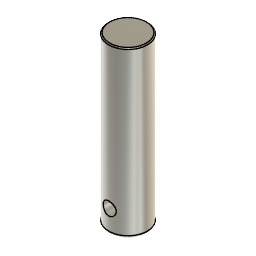
full hammer (Autodesk Fusion 360 archive; units mm, degrees)
design "hammer"
part number: 2025-10-12-17-45-08-986
Autodesk Fusion 360 part; units mm, degrees
sketch "handle" plane through (0, 0, 0) normal (0, 1, 0) x (1, 0, 0)
  line L0 (0, -14.3854) -> (0, -177.8)
  line L1 (0, -177.8) -> (0, -127.8)
  line L2 (0, -177.8) -> (19.05, -177.8)
  line L3 (19.05, -177.8) -> (19.05, -14.3854)
  line L4 (19.05, -14.3854) -> (0, -14.3854)
  dimension "d2" = 177.8
  constraint parallel L0 L1
  constraint perpendicular L1 L2
  constraint perpendicular L3 L4
  measures "d2" distance of origin L0.end
revolve "Revolve1" add sketch "handle" angle 360 about axis through (0, 0, 14.3854) along (0, 0, 1)
fillet "Fillet1" radius 3 1 edges at (-17.7608, -6.8888, 14.3854) 1 faces at (-7.2281, 0.9464, 14.3854)
sketch "hole" plane through (0, 0, 0) normal (0, 1, 0) x (1, 0, 0)
  line L0 (0, 0) -> (0, -32.4031)
  circle A0 centre (0, -32.4031) radius 6.35
  dimension "d10" = 12.7
  constraint coincident L0.start origin
  constraint vertical L0
  constraint coincident L0.end A0.centre
  measures "d10" diameter of A0
hole "Hole2" at (0, -19.05, 32.7368) direction (0, 1, 0) diameter 12.7 end through all
move_face "MoveFace1" to x (1, 0, 0) y (0, 1, 0) z (0, 0, 1) at (0, 0, 15) 1 faces at (8.4885, 17.0543, 76.1675)
move_face "MoveFace2" to x (0.939693, 0, 0.34202) y (0, 1, 0) z (-0.34202, 0, 0.939693) at (11.3236, 0, 11.9735) 1 faces at (1.7932, 6.3315, 26.6452)
move_face "MoveFace3" to x (0.965926, 0, -0.258819) y (0, 1, 0) z (0.258819, 0, 0.965926) at (-11.1135, 0, -3.5106) 1 faces at (-4.0829, 6.1688, 37.982)
fillet "Fillet6" radius 1 1 edges at (-17.7608, -6.8888, 177.8)
move_face "OffsetFaces1" offset -1 1 faces at (-8.3651, -1.4992, 14.3854)
named bodies: "handle"

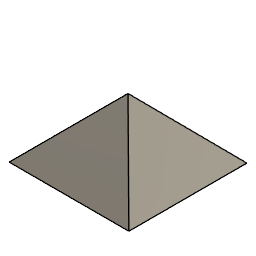
design "spike"
part number: 2025-10-12-19-42-02-121
Autodesk Fusion 360 part; units mm, degrees
sketch "base" plane through (0, 0, 0) normal (0, 0, 1) x (1, 0, 0)
  line L0 (25.4, -25.0465) -> (-25.4, -25.0465)
  line L1 (-25.4, -25.0465) -> (-25.4, 25.0465)
  line L2 (-25.4, 25.0465) -> (25.4, 25.0465)
  line L3 (25.4, 25.0465) -> (25.4, -25.0465)
  line L4 (25.4, -25.0465) -> (-25.4, 25.0465) construction
  line L5 (-25.4, -25.0465) -> (25.4, 25.0465) construction
  dimension "d18" = 50.8
  dimension "d19" = 50.093
  constraint horizontal L0
  constraint perpendicular L0 L1
  constraint parallel L0 L2
  constraint parallel L1 L3
  constraint coincident L4 origin
  constraint coincident L5 origin
  measures "d18" distance of L1.end L2.end
  measures "d19" distance of L0.end L1.end
ref_plane "WorkPlane3" through (0, 0, 25.4) normal (0, 0, 1) x (1, 0, 0)
sketch "Sketch6" plane through (0, 0, 25.4) normal (0, 0, 1) x (1, 0, 0)
loft "Loft2" add profiles "base" section 1 section 2 point at (0, 0, 25.4)

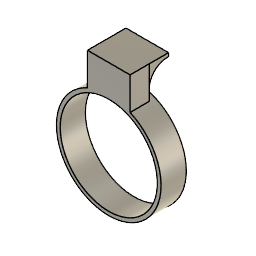
design "rubber band hook"
part number: 2025-11-06-15-43-48-877
Autodesk Fusion 360 part; units mm, degrees
sketch "Sketch1" plane through (0, 0, 0) normal (0, 1, 0) x (1, 0, 0)
  circle A0 centre (0, 0) radius 19.175
  circle A1 centre (0, 0) radius 20.675
  dimension "d1" = 38.35
  dimension "d2" = 41.35
  constraint coincident A0.centre A1.centre
  measures "d1" diameter of A0
  measures "d2" diameter of A1
extrude "Extrude1" add sketch "Sketch1" against normal blind 10
sketch "Sketch3" plane through (0, 0, 0) normal (0, 1, 0) x (1, 0, 0)
  line L0 (8.433, -20.675, -2.38) -> (8.433, -31.729, -2.38)
  line L1 (0, -20.675, -2.38) -> (8.433, -20.675, -2.38)
  line L2 (0, -20.675, -2.38) -> (-8.433, -20.675, -2.38)
  line L3 (-8.433, -18.877, -2.38) -> (-8.433, -20.675, -2.38)
  line L4 (8.433, -18.877, -2.38) -> (8.433, -20.675, -2.38)
  line L5 (8.433, -31.729, -2.38) -> (-8.433, -31.729, -2.38)
  line L6 (-8.433, -31.729, -2.38) -> (-8.433, -20.675, -2.38)
  arc A0 through (-8.433, -18.877, -2.38) (0, -20.675, -2.38) (8.433, -18.877, -2.38)
  dimension "d19" = 11.054
  dimension "d20" = 8.433
  dimension "d21" = 8.433
extrude "Extrude4" add sketch "Sketch3" against normal blind 7.62 contours L0 L1 L2 L5 L6 | L1 L4 A0 | L2 L3 A0 in plane through (0, -2.38, 0) normal (0, 1, 0)
sketch "Sketch7" plane through (-8.433, 0, 0) normal (-1, 0, 0) x (0, -1, 0)
  line L0 (2.38, 31.729) -> (2.38, 18.877)
  line L1 (2.38, 18.877) -> (10, 18.877)
  line L2 (10, 18.877) -> (10, 31.729)
  line L3 (10, 31.729) -> (2.38, 31.729)
  line L4 (2.38, 31.729) -> (-5.24, 31.729)
  line L5 (-5.24, 31.729) -> (-5.24, 30.332)
  line L6 (2.38, 31.729) -> (2.38, 23.195)
  arc A0 (2.38, 23.195) -> (-5.24, 30.332) centre (-4.7723, 23.195) ccw
  dimension "d25" = 7.62
  dimension "d26" = 1.397
  dimension "d27" = 8.534
  constraint coincident L0.start L3.end
  constraint perpendicular L0 L4
  constraint perpendicular L4 L5
  constraint perpendicular L4 L6
  constraint tangent L6 A0
  measures "d25" distance of L0.start L4.end
  measures "d26" distance of L4.end L5.end
  measures "d27" distance of L0.start L6.end
extrude "Extrude5" add sketch "Sketch7" against normal blind 16.8656 contours L0 L4 L5 L6 A0

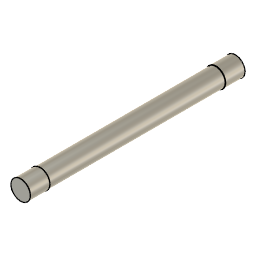
design "rod hammer to base"
part number: 2025-10-21-13-39-30-223
Autodesk Fusion 360 part; units mm, degrees
sketch "Sketch1" plane through (0, 0, 0) normal (0, 1, 0) x (1, 0, 0)
  circle A0 centre (0, 0) radius 6.35
  dimension "d1" = 12.7
  constraint coincident A0.centre origin
  measures "d1" diameter of A0
extrude "Extrude1" add sketch "Sketch1" along normal blind 12.7
sketch "Sketch2" plane through (0, 12.7, 0) normal (0, 1, 0) x (-1, 0, 0)
  circle A0 centre (0, 0) radius 6.35
  circle A1 centre (0, 0) radius 6.15
  dimension "d5" = 12.3
  constraint coincident A0.centre A1.centre
  measures "d5" diameter of A1
extrude "Extrude2" add sketch "Sketch2" along normal blind 114.3 contours A1
sketch "Sketch4" plane through (0, 127, 0) normal (0, 1, 0) x (-1, 0, 0)
  circle A0 centre (0, 0) radius 6.15
  circle A1 centre (0, 0) radius 6.35
  dimension "d8" = 12.7
  constraint concentric A0 A1
  measures "d8" diameter of A1
extrude "Extrude3" add sketch "Sketch4" 1 faces at (-1.2733, 127, -3.6082) along normal blind 12.7 contours A0 | A1
